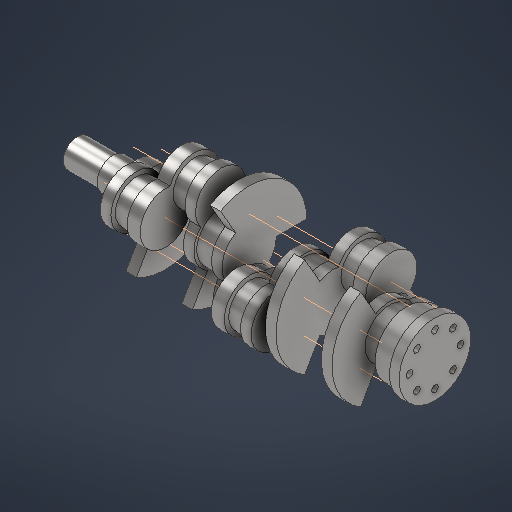
# Autodesk Inventor part: V6_Crankshaft
Saved by Autodesk Inventor 2027.1 (Build 311270010, 270A)
## iProperties
Created: 2026-10-17
Part Number: V6_Crankshaft
Material: Steel, Alloy
Document SubType Name: Modeling
Designer: kashyap
Density: 7.73 g/cm^3
Appearance: Semi-Polished
Mass: 14106.6 g
Surface Area: 2238.88 cm^2
Volume: 1824.92 cm^3
Material_Status: Assumed for this reconstruction
Author: kashyap
Autodesk Inventor part; units mm, degrees
derived "V6_Engine_Master.ipt"
ref_plane "Main_1_Plane" through (-158.25, 0, 0) normal (1, 0, 0) x (0, 1, 0)
ref_plane "Main_2_Plane" through (-52.75, 0, 0) normal (1, 0, 0) x (0, 1, 0)
ref_plane "Main_3_Plane" through (52.75, 0, 0) normal (1, 0, 0) x (0, 1, 0)
ref_plane "Main_4_Plane" through (158.25, 0, 0) normal (1, 0, 0) x (0, 1, 0)
ref_plane "Crankpin_A1_Plane" through (-123.8, 0, 0) normal (1, 0, 0) x (0, 1, 0)
ref_plane "Crankpin_A1_Radial_Plane" through (0, 0, 0) normal (0, 0.8660254, -0.5) x (1, 0, 0)
ref_plane "Crankpin_A1_Offset_Plane" through (0, 20.75, 35.9401) normal (0, 0.5, 0.8660254) x (1, 0, 0)
ref_plane "Crankpin_B1_Plane" through (-87.2, 0, 0) normal (1, 0, 0) x (0, 1, 0)
ref_plane "Crankpin_B1_Radial_Plane" through (0, 0, 0) normal (0, 0, -1) x (1, 0, 0)
ref_plane "Crankpin_B1_Offset_Plane" through (0, 41.5, 0) normal (0, 1, 0) x (1, 0, 0)
ref_plane "Crankpin_A2_Plane" through (-18.3, 0, 0) normal (1, 0, 0) x (0, 1, 0)
ref_plane "Crankpin_A2_Radial_Plane" through (0, 0, 0) normal (0, 0, 1) x (1, 0, 0)
ref_plane "Crankpin_A2_Offset_Plane" through (0, -41.5, 0) normal (0, -1, 0) x (1, 0, 0)
ref_plane "Crankpin_B2_Plane" through (18.3, 0, 0) normal (1, 0, 0) x (0, 1, 0)
ref_plane "Crankpin_B2_Radial_Plane" through (0, 0, 0) normal (0, 0.8660254, 0.5) x (1, 0, 0)
ref_plane "Crankpin_B2_Offset_Plane" through (0, -20.75, 35.9401) normal (0, -0.5, 0.8660254) x (1, 0, 0)
ref_plane "Crankpin_A3_Plane" through (87.2, 0, 0) normal (1, 0, 0) x (0, 1, 0)
ref_plane "Crankpin_A3_Radial_Plane" through (0, 0, 0) normal (0, -0.8660254, -0.5) x (1, 0, 0)
ref_plane "Crankpin_A3_Offset_Plane" through (0, 20.75, -35.9401) normal (0, 0.5, -0.8660254) x (1, 0, 0)
ref_plane "Crankpin_B3_Plane" through (123.8, 0, 0) normal (1, 0, 0) x (0, 1, 0)
ref_plane "Crankpin_B3_Radial_Plane" through (0, 0, 0) normal (0, -0.8660254, 0.5) x (1, 0, 0)
ref_plane "Crankpin_B3_Offset_Plane" through (0, -20.75, -35.9401) normal (0, -0.5, -0.8660254) x (1, 0, 0)
sketch "SK_Main_Journal_1" plane through (-158.25, 0, 0) normal (1, 0, 0) x (0, 1, 0)
  circle A0 centre (0, 0) radius 30.5
  dimension "d47" = 61
  constraints: 1 centre point
  measures "d47" diameter of A0
extrude "Main_Journal_1" add sketch "SK_Main_Journal_1" along normal mid plane 22
sketch "SK_Main_Journal_2" plane through (-52.75, 0, 0) normal (1, 0, 0) x (0, 1, 0)
  circle A0 centre (0, 0) radius 30.5
  dimension "d50" = 61
  constraints: 1 centre point
  measures "d50" diameter of A0
extrude "Main_Journal_2" add sketch "SK_Main_Journal_2" along normal mid plane 22
sketch "SK_Main_Journal_3" plane through (52.75, 0, 0) normal (1, 0, 0) x (0, 1, 0)
  circle A0 centre (0, 0) radius 30.5
  dimension "d53" = 61
  constraints: 1 centre point
  measures "d53" diameter of A0
extrude "Main_Journal_3" add sketch "SK_Main_Journal_3" along normal mid plane 22
sketch "SK_Main_Journal_4" plane through (158.25, 0, 0) normal (1, 0, 0) x (0, 1, 0)
  circle A0 centre (0, 0) radius 30.5
  dimension "d56" = 61
  constraints: 1 centre point
  measures "d56" diameter of A0
extrude "Main_Journal_4" add sketch "SK_Main_Journal_4" along normal mid plane 22
sketch "SK_Crankpin_A1" plane through (-123.8, 0, 0) normal (1, 0, 0) x (0, 1, 0)
  circle A0 centre (20.75, 35.9401) radius 26.5
  dimension "d59" = 53
  constraints: 1 centre point
  measures "d59" diameter of A0
extrude "Crankpin_A1" add sketch "SK_Crankpin_A1" along normal mid plane 20.3
sketch "SK_Crankpin_B1" plane through (-87.2, 0, 0) normal (1, 0, 0) x (0, 1, 0)
  circle A0 centre (41.5, 0) radius 26.5
  dimension "d62" = 53
  constraints: 1 centre point
  measures "d62" diameter of A0
extrude "Crankpin_B1" add sketch "SK_Crankpin_B1" along normal mid plane 20.3
sketch "SK_Crankpin_A2" plane through (-18.3, 0, 0) normal (1, 0, 0) x (0, 1, 0)
  circle A0 centre (-41.5, 0) radius 26.5
  dimension "d65" = 53
  constraints: 1 centre point
  measures "d65" diameter of A0
extrude "Crankpin_A2" add sketch "SK_Crankpin_A2" along normal mid plane 20.3
sketch "SK_Crankpin_B2" plane through (18.3, 0, 0) normal (1, 0, 0) x (0, 1, 0)
  circle A0 centre (-20.75, 35.9401) radius 26.5
  dimension "d68" = 53
  constraints: 1 centre point
  measures "d68" diameter of A0
extrude "Crankpin_B2" add sketch "SK_Crankpin_B2" along normal mid plane 20.3
sketch "SK_Crankpin_A3" plane through (87.2, 0, 0) normal (1, 0, 0) x (0, 1, 0)
  circle A0 centre (20.75, -35.9401) radius 26.5
  dimension "d71" = 53
  constraints: 1 centre point
  measures "d71" diameter of A0
extrude "Crankpin_A3" add sketch "SK_Crankpin_A3" along normal mid plane 20.3
sketch "SK_Crankpin_B3" plane through (123.8, 0, 0) normal (1, 0, 0) x (0, 1, 0)
  circle A0 centre (-20.75, -35.9401) radius 26.5
  dimension "d74" = 53
  constraints: 1 centre point
  measures "d74" diameter of A0
extrude "Crankpin_B3" add sketch "SK_Crankpin_B3" along normal mid plane 20.3
ref_plane "Web_1F_Plane" through (-147.25, 0, 0) normal (1, 0, 0) x (0, 1, 0)
sketch "SK_Web_1F" plane through (-147.25, 0, 0) normal (1, 0, 0) x (0, 1, 0)
  circle A0 centre (0, 0) radius 34
  circle A1 centre (20.75, 35.9401) radius 32
  dimension "d78" = 68
  dimension "d79" = 64
  constraints: 2 centre point
  measures "d78" diameter of A0
  measures "d79" diameter of A1
extrude "Web_1F" add sketch "SK_Web_1F" along normal blind 13.3
ref_plane "Web_1R_Plane" through (-63.75, 0, 0) normal (1, 0, 0) x (0, 1, 0)
sketch "SK_Web_1R" plane through (-63.75, 0, 0) normal (1, 0, 0) x (0, 1, 0)
  circle A0 centre (0, 0) radius 34
  circle A1 centre (41.5, 0) radius 32
  dimension "d83" = 68
  dimension "d84" = 64
  constraints: 2 centre point
  measures "d83" diameter of A0
  measures "d84" diameter of A1
extrude "Web_1R" add sketch "SK_Web_1R" against normal blind 13.3
ref_plane "Web_2F_Plane" through (-41.75, 0, 0) normal (1, 0, 0) x (0, 1, 0)
sketch "SK_Web_2F" plane through (-41.75, 0, 0) normal (1, 0, 0) x (0, 1, 0)
  circle A0 centre (0, 0) radius 34
  circle A1 centre (-41.5, 0) radius 32
  dimension "d88" = 68
  dimension "d89" = 64
  constraints: 2 centre point
  measures "d88" diameter of A0
  measures "d89" diameter of A1
extrude "Web_2F" add sketch "SK_Web_2F" along normal blind 13.3
ref_plane "Web_2R_Plane" through (41.75, 0, 0) normal (1, 0, 0) x (0, 1, 0)
sketch "SK_Web_2R" plane through (41.75, 0, 0) normal (1, 0, 0) x (0, 1, 0)
  circle A0 centre (0, 0) radius 34
  circle A1 centre (-20.75, 35.9401) radius 32
  dimension "d93" = 68
  dimension "d94" = 64
  constraints: 2 centre point
  measures "d93" diameter of A0
  measures "d94" diameter of A1
extrude "Web_2R" add sketch "SK_Web_2R" against normal blind 13.3
ref_plane "Web_3F_Plane" through (63.75, 0, 0) normal (1, 0, 0) x (0, 1, 0)
sketch "SK_Web_3F" plane through (63.75, 0, 0) normal (1, 0, 0) x (0, 1, 0)
  circle A0 centre (0, 0) radius 34
  circle A1 centre (20.75, -35.9401) radius 32
  dimension "d98" = 68
  dimension "d99" = 64
  constraints: 2 centre point
  measures "d98" diameter of A0
  measures "d99" diameter of A1
extrude "Web_3F" add sketch "SK_Web_3F" along normal blind 13.3
ref_plane "Web_3R_Plane" through (147.25, 0, 0) normal (1, 0, 0) x (0, 1, 0)
sketch "SK_Web_3R" plane through (147.25, 0, 0) normal (1, 0, 0) x (0, 1, 0)
  circle A0 centre (0, 0) radius 34
  circle A1 centre (-20.75, -35.9401) radius 32
  dimension "d103" = 68
  dimension "d104" = 64
  constraints: 2 centre point
  measures "d103" diameter of A0
  measures "d104" diameter of A1
extrude "Web_3R" add sketch "SK_Web_3R" against normal blind 13.3
ref_plane "Split_Web_1_Plane" through (-105.5, 0, 0) normal (1, 0, 0) x (0, 1, 0)
sketch "SK_Split_Web_1" plane through (-105.5, 0, 0) normal (1, 0, 0) x (0, 1, 0)
  circle A0 centre (20.75, 35.9401) radius 32
  circle A1 centre (41.5, 0) radius 32
  dimension "d108" = 64
  dimension "d109" = 64
  constraints: 2 centre point
  measures "d108" diameter of A0
  measures "d109" diameter of A1
extrude "Split_Web_1" add sketch "SK_Split_Web_1" along normal mid plane 16.3
ref_plane "Split_Web_2_Plane" through (0, 0, 0) normal (1, 0, 0) x (0, 1, 0)
sketch "SK_Split_Web_2" plane through (0, 0, 0) normal (1, 0, 0) x (0, 1, 0)
  circle A0 centre (-41.5, 0) radius 32
  circle A1 centre (-20.75, 35.9401) radius 32
  dimension "d113" = 64
  dimension "d114" = 64
  constraints: 2 centre point
  measures "d113" diameter of A0
  measures "d114" diameter of A1
extrude "Split_Web_2" add sketch "SK_Split_Web_2" along normal mid plane 16.3
ref_plane "Split_Web_3_Plane" through (105.5, 0, 0) normal (1, 0, 0) x (0, 1, 0)
sketch "SK_Split_Web_3" plane through (105.5, 0, 0) normal (1, 0, 0) x (0, 1, 0)
  circle A0 centre (20.75, -35.9401) radius 32
  circle A1 centre (-20.75, -35.9401) radius 32
  dimension "d118" = 64
  dimension "d119" = 64
  constraints: 2 centre point
  measures "d118" diameter of A0
  measures "d119" diameter of A1
extrude "Split_Web_3" add sketch "SK_Split_Web_3" along normal mid plane 16.3
ref_plane "Counterweight_1_Dir_Plane" through (0, 0, 0) normal (0, -0.5, 0.8660254) x (1, 0, 0)
ref_plane "Counterweight_2_Dir_Plane" through (0, 0, 0) normal (0, -0.5, -0.8660254) x (1, 0, 0)
ref_plane "Counterweight_3_Dir_Plane" through (0, 0, 0) normal (0, 1, 0) x (1, 0, 0)
sketch "SK_Counterweight_1" plane through (-147.25, 0, 0) normal (1, 0, 0) x (0, 1, 0)
  line L0 (-134.0607, -77.4) -> (40.53, 23.4) construction
  line L1 (0, 0) -> (-62.3538, 36)
  line L2 (0, 0) -> (0, -72)
  arc A0 (-62.3538, 36) -> (0, -72) centre (0, 0) ccw
  dimension "d125" = 72
  dimension "d126" = 60
  dimension "d127" = 60
  constraints: 4 end point, 2 point on circle, 1 centre point
  measures "d125" radius of A0
  measures "d126" angle of L0 L1
  measures "d127" angle of L0 L2
extrude "Counterweight_1_NOT_BALANCE_VERIFIED" add sketch "SK_Counterweight_1" along normal blind 13.3
sketch "SK_Counterweight_2" plane through (-63.75, 0, 0) normal (1, 0, 0) x (0, 1, 0)
  line L0 (-134.0607, -77.4) -> (40.53, 23.4) construction
  line L1 (0, 0) -> (-62.3538, 36)
  line L2 (0, 0) -> (0, -72)
  arc A0 (-62.3538, 36) -> (0, -72) centre (0, 0) ccw
  dimension "d130" = 72
  dimension "d131" = 60
  dimension "d132" = 60
  constraints: 4 end point, 2 point on circle, 1 centre point
  measures "d130" radius of A0
  measures "d131" angle of L0 L1
  measures "d132" angle of L0 L2
extrude "Counterweight_2_NOT_BALANCE_VERIFIED" add sketch "SK_Counterweight_2" against normal blind 13.3
sketch "SK_Counterweight_3" plane through (-41.75, 0, 0) normal (1, 0, 0) x (0, 1, 0)
  line L0 (134.0607, -77.4) -> (-40.53, 23.4) construction
  line L1 (0, 0) -> (0, -72)
  line L2 (0, 0) -> (62.3538, 36)
  arc A0 (0, -72) -> (62.3538, 36) centre (0, 0) ccw
  dimension "d135" = 72
  dimension "d136" = 60
  dimension "d137" = 60
  constraints: 4 end point, 2 point on circle, 1 centre point
  measures "d135" radius of A0
  measures "d136" angle of L0 L1
  measures "d137" angle of L0 L2
extrude "Counterweight_3_NOT_BALANCE_VERIFIED" add sketch "SK_Counterweight_3" along normal blind 13.3
sketch "SK_Counterweight_4" plane through (63.75, 0, 0) normal (1, 0, 0) x (0, 1, 0)
  line L0 (0, 86.4) -> (0, -14.4) construction
  line L1 (0, 0) -> (62.3538, 36)
  line L2 (0, 0) -> (-62.3538, 36)
  arc A0 (62.3538, 36) -> (-62.3538, 36) centre (0, 0) ccw
  dimension "d140" = 72
  dimension "d141" = 60
  dimension "d142" = 60
  constraints: 4 end point, 2 point on circle, 1 centre point
  measures "d140" radius of A0
  measures "d141" angle of L0 L1
  measures "d142" angle of L0 L2
extrude "Counterweight_4_NOT_BALANCE_VERIFIED" add sketch "SK_Counterweight_4" along normal blind 13.3
sketch "SK_Counterweight_5" plane through (147.25, 0, 0) normal (1, 0, 0) x (0, 1, 0)
  line L0 (0, 86.4) -> (0, -14.4) construction
  line L1 (0, 0) -> (62.3538, 36)
  line L2 (0, 0) -> (-62.3538, 36)
  arc A0 (62.3538, 36) -> (-62.3538, 36) centre (0, 0) ccw
  dimension "d145" = 72
  dimension "d146" = 60
  dimension "d147" = 60
  constraints: 4 end point, 2 point on circle, 1 centre point
  measures "d145" radius of A0
  measures "d146" angle of L0 L1
  measures "d147" angle of L0 L2
extrude "Counterweight_5_NOT_BALANCE_VERIFIED" add sketch "SK_Counterweight_5" against normal blind 13.3
ref_plane "Snout_Sprocket_Start_Plane" through (-169.25, 0, 0) normal (1, 0, 0) x (0, 1, 0)
sketch "SK_Snout_Sprocket" plane through (-169.25, 0, 0) normal (1, 0, 0) x (0, 1, 0)
  circle A0 centre (0, 0) radius 20
  dimension "d151" = 40
  constraints: 1 centre point
  measures "d151" diameter of A0
extrude "Snout_Sprocket" add sketch "SK_Snout_Sprocket" against normal blind 30
ref_plane "Snout_Pulley_Start_Plane" through (-199.25, 0, 0) normal (1, 0, 0) x (0, 1, 0)
sketch "SK_Snout_Pulley" plane through (-199.25, 0, 0) normal (1, 0, 0) x (0, 1, 0)
  circle A0 centre (0, 0) radius 17.5
  dimension "d155" = 35
  constraints: 1 centre point
  measures "d155" diameter of A0
extrude "Snout_Pulley" add sketch "SK_Snout_Pulley" against normal blind 45
ref_plane "Rear_Seal_Hub_Start_Plane" through (169.25, 0, 0) normal (1, 0, 0) x (0, 1, 0)
sketch "SK_Rear_Seal_Hub" plane through (169.25, 0, 0) normal (1, 0, 0) x (0, 1, 0)
  circle A0 centre (0, 0) radius 40
  dimension "d159" = 80
  constraints: 1 centre point
  measures "d159" diameter of A0
extrude "Rear_Seal_Hub" add sketch "SK_Rear_Seal_Hub" along normal blind 23
ref_plane "Rear_Flange_Start_Plane" through (192.25, 0, 0) normal (1, 0, 0) x (0, 1, 0)
sketch "SK_Rear_Flange" plane through (192.25, 0, 0) normal (1, 0, 0) x (0, 1, 0)
  circle A0 centre (0, 0) radius 45
  dimension "d163" = 90
  constraints: 1 centre point
  measures "d163" diameter of A0
extrude "Rear_Flange" add sketch "SK_Rear_Flange" along normal blind 12
ref_plane "Rear_Flange_Face_Plane" through (204.25, 0, 0) normal (1, 0, 0) x (0, 1, 0)
sketch "SK_Flywheel_Bolt" plane through (204.25, 0, 0) normal (1, 0, 0) x (0, 1, 0)
  line L0 (0, 38.4) -> (0, -6.4) construction
  point P0 (0, 0)
  point P1 (0, 32)
  dimension "d175" = 32
  constraints: 1 point on line
  measures "d175" distance of point (0, 0) point (0, 32)
hole "Flywheel_Bolt_Hole" at (204.25, 0, 32) direction (-1, 0, 0) diameter 8.5 depth 18 tip angle 118
pattern_circular "Flywheel_Bolt_Pattern" count 8 over 360 about axis through (0, 0, 0) along (-1, 0, 0) of "Flywheel_Bolt_Hole"
ref_plane "Crankpin_A1_Normal_Plane" through (0, 0, 0) normal (0, 0.5, 0.8660254) x (1, 0, 0)
ref_plane "Crankpin_B1_Normal_Plane" through (0, 0, 0) normal (0, 1, 0) x (1, 0, 0)
ref_plane "Crankpin_A2_Normal_Plane" through (0, 0, 0) normal (0, -1, 0) x (1, 0, 0)
ref_plane "Crankpin_B2_Normal_Plane" through (0, 0, 0) normal (0, -0.5, 0.8660254) x (1, 0, 0)
ref_plane "Crankpin_A3_Normal_Plane" through (0, 0, 0) normal (0, 0.5, -0.8660254) x (1, 0, 0)
ref_plane "Crankpin_B3_Normal_Plane" through (0, 0, 0) normal (0, -0.5, -0.8660254) x (1, 0, 0)
equation "\"d47\" = Main_Journal_Diameter"
equation "\"d48\" = Main_Journal_Width"
equation "\"d50\" = Main_Journal_Diameter"
equation "\"d51\" = Main_Journal_Width"
equation "\"d53\" = Main_Journal_Diameter"
equation "\"d54\" = Main_Journal_Width"
equation "\"d56\" = Main_Journal_Diameter"
equation "\"d57\" = Main_Journal_Width"
equation "\"d59\" = Crankpin_Diameter"
equation "\"d60\" = Crankpin_Width"
equation "\"d62\" = Crankpin_Diameter"
equation "\"d63\" = Crankpin_Width"
equation "\"d65\" = Crankpin_Diameter"
equation "\"d66\" = Crankpin_Width"
equation "\"d68\" = Crankpin_Diameter"
equation "\"d69\" = Crankpin_Width"
equation "\"d71\" = Crankpin_Diameter"
equation "\"d72\" = Crankpin_Width"
equation "\"d74\" = Crankpin_Diameter"
equation "\"d75\" = Crankpin_Width"
equation "\"d78\" = 2 * Crank_Web_Boss_Radius"
equation "\"d79\" = 2 * Crank_Pin_Boss_Radius"
equation "\"d80\" = Crank_Web_Thickness"
equation "\"d83\" = 2 * Crank_Web_Boss_Radius"
equation "\"d84\" = 2 * Crank_Pin_Boss_Radius"
equation "\"d85\" = Crank_Web_Thickness"
equation "\"d88\" = 2 * Crank_Web_Boss_Radius"
equation "\"d89\" = 2 * Crank_Pin_Boss_Radius"
equation "\"d90\" = Crank_Web_Thickness"
equation "\"d93\" = 2 * Crank_Web_Boss_Radius"
equation "\"d94\" = 2 * Crank_Pin_Boss_Radius"
equation "\"d95\" = Crank_Web_Thickness"
equation "\"d98\" = 2 * Crank_Web_Boss_Radius"
equation "\"d99\" = 2 * Crank_Pin_Boss_Radius"
equation "\"d100\" = Crank_Web_Thickness"
equation "\"d103\" = 2 * Crank_Web_Boss_Radius"
equation "\"d104\" = 2 * Crank_Pin_Boss_Radius"
equation "\"d105\" = Crank_Web_Thickness"
equation "\"d108\" = 2 * Crank_Pin_Boss_Radius"
equation "\"d109\" = 2 * Crank_Pin_Boss_Radius"
equation "\"d110\" = Split_Web_Thickness"
equation "\"d113\" = 2 * Crank_Pin_Boss_Radius"
equation "\"d114\" = 2 * Crank_Pin_Boss_Radius"
equation "\"d115\" = Split_Web_Thickness"
equation "\"d118\" = 2 * Crank_Pin_Boss_Radius"
equation "\"d119\" = 2 * Crank_Pin_Boss_Radius"
equation "\"d120\" = Split_Web_Thickness"
equation "\"d125\" = Counterweight_Radius"
equation "\"d126\" = Counterweight_Half_Angle"
equation "\"d127\" = Counterweight_Half_Angle"
equation "\"d128\" = Crank_Web_Thickness"
equation "\"d130\" = Counterweight_Radius"
equation "\"d131\" = Counterweight_Half_Angle"
equation "\"d132\" = Counterweight_Half_Angle"
equation "\"d133\" = Crank_Web_Thickness"
equation "\"d135\" = Counterweight_Radius"
equation "\"d136\" = Counterweight_Half_Angle"
equation "\"d137\" = Counterweight_Half_Angle"
equation "\"d138\" = Crank_Web_Thickness"
equation "\"d140\" = Counterweight_Radius"
equation "\"d141\" = Counterweight_Half_Angle"
equation "\"d142\" = Counterweight_Half_Angle"
equation "\"d143\" = Crank_Web_Thickness"
equation "\"d145\" = Counterweight_Radius"
equation "\"d146\" = Counterweight_Half_Angle"
equation "\"d147\" = Counterweight_Half_Angle"
equation "\"d148\" = Crank_Web_Thickness"
equation "\"d151\" = Snout_Sprocket_Dia"
equation "\"d152\" = Snout_Sprocket_Length"
equation "\"d155\" = Snout_Pulley_Dia"
equation "\"d156\" = Snout_Pulley_Length"
equation "\"d159\" = Rear_Seal_Hub_Dia"
equation "\"d160\" = Rear_Seal_Hub_Length"
equation "\"d163\" = Rear_Flange_Dia"
equation "\"d164\" = Rear_Flange_Thickness"
equation "\"d175\" = 0.5 * Flywheel_Bolt_PCD"
equation "\"d176\" = Flywheel_Bolt_Tap_Dia"
equation "\"d181\" = Flywheel_Bolt_Depth"
equation "\"Main_Journal_Diameter\" = 61"
equation "\"Main_Journal_Width\" = 22"
equation "\"Crankpin_Diameter\" = 53"
equation "\"Crankpin_Width\" = 20.3"
equation "\"Crank_Web_Boss_Radius\" = 34"
equation "\"Crank_Pin_Boss_Radius\" = 32"
equation "\"Crank_Web_Thickness\" = 13.3"
equation "\"Split_Web_Thickness\" = 16.3"
equation "\"Counterweight_Radius\" = 72"
equation "\"Counterweight_Half_Angle\" = 60deg"
equation "\"Snout_Sprocket_Dia\" = 40"
equation "\"Snout_Sprocket_Length\" = 30"
equation "\"Snout_Pulley_Dia\" = 35"
equation "\"Snout_Pulley_Length\" = 45"
equation "\"Rear_Seal_Hub_Dia\" = 80"
equation "\"Rear_Seal_Hub_Length\" = 23"
equation "\"Rear_Flange_Dia\" = 90"
equation "\"Rear_Flange_Thickness\" = 12"
equation "\"Flywheel_Bolt_Tap_Dia\" = 8.5"
equation "\"Flywheel_Bolt_Depth\" = 18"
equation "\"Flywheel_Bolt_PCD\" = 64"
body "Solid1"
